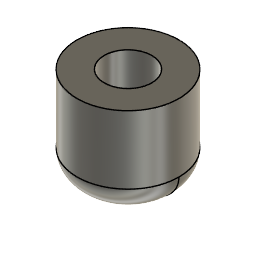
M8_bolt_damper (Autodesk Fusion 360 design; units mm, degrees)
part number: 2026-10-18-12-58-33-534
Autodesk Fusion 360 part; units mm, degrees
sketch "Sketch1" plane through (0, 0, 0) normal (0, 0, 1) x (1, 0, 0)
  circle A0 centre (0, 0) radius 3.5
  circle A1 centre (0, 0) radius 7.5
  dimension "d1" = 7
  dimension "d2" = 15
  constraint coincident A0.centre A1.centre
  measures "d1" diameter of A0
  measures "d2" diameter of A1
extrude "Extrude1" add sketch "Sketch1" along normal blind 10
sketch "Sketch2" plane through (0, 0, 0) normal (0, 1, 0) x (1, 0, 0)
  ellipse E0 centre (0, 0) end of major axis (0, 5) minor radius 7.5
  line L0 (0, -5) -> (0, 5) construction
  line L1 (7.5, 0) -> (-7.5, 0) construction
  line L2 (-7.5, -10) -> (7.5, -10)
  line L3 (-7.5, 0) -> (7.5, 0)
  line L4 (0, 0) -> (0, 5)
  dimension "d5" = 10
  constraint coincident E0 L0.start
  constraint coincident E0 L0.end
  constraint coincident E0 L1.start
  constraint coincident E0 L1.end
  constraint coincident E0.centre L4.start
  constraint vertical L0
  constraint coincident L1.start L3.end
  constraint coincident L0.end L4.end
  measures "d5" distance of E0
revolve "Revolve1" add sketch "Sketch2" angle 360 about axis through (0, 0, 5) along (0, 0, -1) contours E0 L3 L4 picked at (4.8146, 0.6299)
